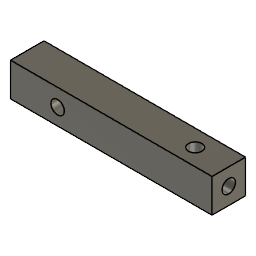
supporto_sensori_hcsr04_v2 (Autodesk Fusion 360 design; units mm, degrees)
Autodesk Fusion 360 part; units mm, degrees
sketch "Schizzo1" plane through (0, 0, 0) normal (0, 0, 1) x (1, 0, 0)
  line L0 (-50, 15) -> (10, 15)
  line L1 (10, 15) -> (10, 5)
  line L2 (10, 5) -> (-50, 5)
  line L3 (-50, 5) -> (-50, 15)
  circle A0 centre (0, 10) radius 2
  dimension "d1" = 60
  dimension "d2" = 10
  dimension "d3" = 4
  constraint horizontal L0
  constraint vertical L1
  constraint horizontal L2
  constraint vertical L3
  measures "d1" distance of L0.start L0.end
  measures "d2" distance of L0.start L2.end
  measures "d3" diameter of A0
extrude "Estrusione1" add sketch "Schizzo1" along normal blind 10
hole "Foratura1" at (-50, 10, 5) direction (1, 0, 0) diameter 4 depth 5 tip angle 118
hole "Foratura2" at (-35.9517, 15, 4.8742) direction (0, -1, 0) diameter 4 depth 13 tip angle 118
hole "Foratura3" at (-50, 10, 5) direction (1, 0, 0) diameter 4 depth 12 tip angle 118
hole "Foratura4" at (10, 10, 5) direction (-1, 0, 0) diameter 4 depth 9 tip angle 118
